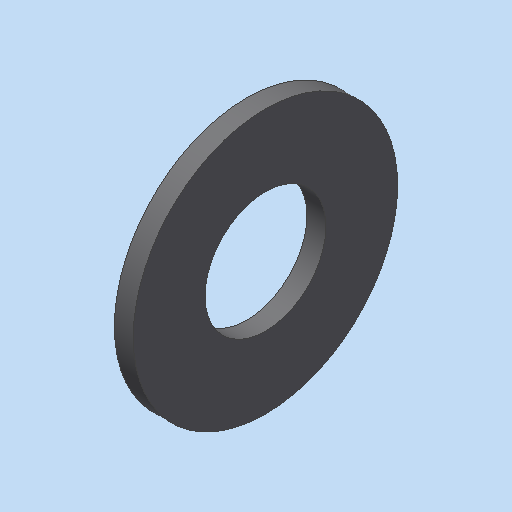
# Autodesk Inventor part: Scheibe_DIN_125_1_A_3_2
Saved by Autodesk Inventor 2023.3 (Build 273359000, 359)
## iProperties
Shininess: 64.0
Length Units: 11269
Angle Units: 11279
Time Units: 11290
Mass Units: 11283
Length Display Precision: 3
Angle Display Precision: 2
Compacted: True
Part Number: Scheibe_DIN_125_1_A_3_2
Document SubType Name: Modeling
Created: 2004-04-25
Description: =<RBPARTNOTITLE2>
Vendor: NORM8
Designer: C.Fischer
Manufacturer: Standard
Standards Organization: Custom
Material: xStahl_AnP_Dummymaterial
Density: 7.85 g/cm^3
Appearance: Stahl - normal AnP
DOC_ID: 5 F45 Scheibe_DIN_125_1_A_3_2
GAIN_REFID: 20__Scheibe_DIN_125_1_A_3_2:CBE8E
Control State: 0
Master: False
Checked Out: False
CNS_NB: Scheibe DIN 125-1-A-3.2
CNS_NN: DIN 125-A - Teil 1
CNS_NT: Scheiben, Produktklasse A, bis Haerte 250 HV, vorzugsweise fuer Sechskantschrauben und -muttern
CNS_NBSYN: Scheibe DIN 125-1-A-$NENN.
CNS_LINA: Scheibe DIN 125-1-A-3.2
CNS_D: 3.000
CNS_DA: 3.200
CNS_DW: 7.000
CNS_H: 0.500
CNS_NENN: 3.2
CNS_KT: X
PSOL_IDENT_0: {C:\partsolutions\data\23d-libs\bosch_bamberg\zubehoer\scheiben\din_125_teil_1_a.prj},153 {VTYP=3D},
PSOL_IDENT_1: {NB=Scheibe DIN 125-1-A-3.2},{NN=DIN 125-A - Teil 1},{DATE=26.11.2003},{GEOMDATE=26.11.2003},{VERSIO
PSOL_IDENT_2: N=v1},{LINEID=70},{LINESUBID=-1},{WBVAR=}  {NB=Scheibe DIN 125-1-A-3.2},{LINA=Scheibe DIN 125-1-A-3.
PSOL_IDENT_3: 2},{KT=X},{IDNR=},{D=3.000},{DA=3.200},{DW=7.000},{H=0.500},{NENN=3.2}
DEF_STKID: T19818
Bezeichnung1: Scheibe DIN 125-1-A-3.2
Bezeichnung2: Scheiben, Produktklasse A, bis Haerte 2
RBDRAWINGMISSINGSPEC: --
RBPARTNOTITLE1: Washer
RBPARTNOTITLE2: Scheibe
AnP_Katogorie: 4
AnP_Kategorie: 4
RBPARTMADEOF: DIN 125-1 - A  3.2 - 140 HV
Density: 0.0
Volumn: 0.0
Area: 0.0
PropertySet Name: Model Information
Title: Scheibe DIN 125-1-A-3.2
Author: C.Fischer
Keywords: =<RBPARTMADEOF>
Comments: =<RBSURFACE2>
Revision Number: 01
Autodesk Inventor part; units mm, degrees
sketch "Sketch_1" plane through (0, 0, 0) normal (0, 0, 1) x (1, 0, 0)
  line L0 (0.5, 0) -> (0, 0)
  line L1 (0, 1.6) -> (0.5, 1.6)
  line L2 (0.5, 1.6) -> (0.5, 3.5)
  line L3 (0.5, 3.5) -> (0, 3.5)
  line L4 (0, 3.5) -> (0, 1.6)
  constraints: 10 end point
revolve "Revolution1" add sketch "Sketch_1" angle 360 about axis through (0.5, 0, 0) along (-1, 0, 0)
ref_plane "IP1_XY" through (0, 0, 0) normal (1, 0, 0) x (0, 0, -1)
ref_plane "IP1_YZ" through (0, 0, 0) normal (0, 0, -1) x (0, 1, 0)
ref_plane "IP2_XY" through (0.5, 0, 0) normal (1, 0, 0) x (0, 0, -1)
ref_plane "IP2_YZ" through (0.5, 0, 0) normal (0, 0, -1) x (0, 1, 0)
